Autodesk Inventor part; units mm, degrees
(part 2 of 2)
sketch "Boceto20" plane through (0, 0, -9.5) normal (0, 0, -1) x (-1, 0, 0)
  line L0 (-0.5, -3.5) -> (45.9, -3.5) projected
  arc A0 (-0.5, -3.5) -> (-2.5, -5.5) centre (-0.5, -5.5) ccw projected
  line L1 (-2.5, -61.9227) -> (-2.5, -5.5) projected
  arc A1 (-2.5, -61.9227) -> (0.5416, -65.8062) centre (1.5, -61.9227) ccw projected
  arc A2 (0.5416, -65.8062) -> (44.8584, -65.8062) centre (22.7, 23.98) ccw projected
  arc A3 (44.8584, -65.8062) -> (47.9, -61.9227) centre (43.9, -61.9227) ccw projected
  line L2 (47.9, -5.5) -> (47.9, -61.9227) projected
  arc A4 (47.9, -5.5) -> (45.9, -3.5) centre (45.9, -5.5) ccw projected
  line L3 (24.0719, -22.2185) -> (24.0719, -54.2185) construction
  line L4 (19.0719, -22.2185) -> (19.0719, -54.2185)
  line L5 (29.0719, -54.2185) -> (29.0719, -22.2185)
  arc A5 (29.0719, -22.2185) -> (19.0719, -22.2185) centre (24.0719, -22.2185) ccw
  arc A6 (19.0719, -54.2185) -> (29.0719, -54.2185) centre (24.0719, -54.2185) ccw
  circle A7 centre (24.0719, -54.2185) radius 2.5
  circle A8 centre (24.0719, -22.2185) radius 2.5
  point P0 (0, 0)
  point P1 (24.0719, -38.2185)
  dimension "d126" = 16
  dimension "d127" = 10
  dimension "d128" = 5
  dimension "d129" = 5
  constraints: 8 end point, 4 centre point, 4 point on circle, 4 tangent, 2 coincident, 1 midpoint, 1 parallel, 1 vertical
  measures "d126" distance of point (24.072, -38.218) L3.end
  measures "d127" diameter of A6
  measures "d128" diameter of A7
  measures "d129" diameter of A8
extrude "Extrusión17" cut sketch "Boceto20" against normal blind 1 contours A5 L5 A6 L4
sketch "Boceto21" plane through (-49.9, -61.9227, 23) normal (-1, 0, 0) x (0, 0, 1)
  line L0 (-5, 50.4227) -> (-9, 50.4227)
  line L1 (-9, 50.4227) -> (-9, 41.9227)
  line L2 (-9, 41.9227) -> (-5, 41.9227)
  line L3 (-5, 41.9227) -> (-5, 50.4227)
  line L4 (0, 56.4227) -> (0, 0) projected
  line L5 (0, 56.4227) -> (-32.5, 56.4227) projected
  point P0 (-23, 61.9227)
  point P1 (-28, 56.4227)
  dimension "d132" = 4
  dimension "d133" = 8.5
  dimension "d134" = 5
  dimension "d135" = 6
  constraints: 8 end point, 2 parallel, 1 horizontal, 1 perpendicular
  measures "d132" distance of L2.end L1.end
  measures "d133" distance of L2.end L0.start
  measures "d134" distance between parallel lines of L4 L3
  measures "d135" distance between parallel lines of L5 L0
extrude "Extrusión18" cut sketch "Boceto21" against normal up to surface (1.4 mm away)
sketch "Boceto23" plane through (-48.5, -33.8, 20) normal (1, 0, 0) x (0, 0, -1)
  line L0 (2, 13.8) -> (6, 13.8) projected
  line L1 (2, 22.3) -> (2, 13.8) projected
  line L2 (6, 13.8) -> (6, 22.3) projected
  line L3 (6, 22.3) -> (2, 22.3) projected
  line L4 (2.1, 13.9) -> (5.9, 13.9)
  line L5 (5.9, 13.9) -> (5.9, 22.2)
  line L6 (5.9, 22.2) -> (2.1, 22.2)
  line L7 (2.1, 22.2) -> (2.1, 13.9)
  line L8 (1.5, 13.3) -> (6.5, 13.3)
  line L9 (6.5, 13.3) -> (6.5, 22.8)
  line L10 (6.5, 22.8) -> (1.5, 22.8)
  line L11 (1.5, 22.8) -> (1.5, 13.3)
  line L12 (3.1, 19.95) -> (4.9, 19.95)
  line L13 (4.9, 19.95) -> (4.9, 16.15)
  line L14 (4.9, 16.15) -> (3.1, 16.15)
  line L15 (3.1, 16.15) -> (3.1, 19.95)
  line L16 (3.1, 19.95) -> (4.9, 16.15) construction
  line L17 (5.9, 22.2) -> (2.1, 13.9) construction
  point P0 (20, 33.8)
  point P1 (4, 18.05)
  dimension "d140" = 0.1
  dimension "d141" = 0.5
  dimension "d146" = 3.8
  dimension "d147" = 1.8
  constraints: 28 end point, 2 midpoint, 2 parallel, 1 horizontal, 1 perpendicular, 6 other
  measures "d140" distance between parallel lines of L1 L7
  measures "d141" distance between parallel lines of L1 L11
  measures "d146" distance of L14.end L12.start
  measures "d147" distance of L12.start L12.end
extrude "Extrusión20" add sketch "Boceto23" along normal blind 4 contours L1 L3 L2 L0 | L11 L10 L9 L8
extrude "Extrusión21" add sketch "Boceto23" against normal up to surface (1.4 mm away) contours L1 L3 L2 L0 | L7 L6 L5 L4
chamfer "Chaflán6" distance 0.4 angle 45 4 edges at (-49.9, -15.75, 15.1) (-49.9, -15.75, 16.9) (-49.9, -17.65, 16) (-49.9, -13.85, 16)
